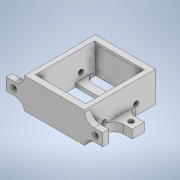
# Autodesk Inventor part: Part1
Saved by Autodesk Inventor 2022.6 (Build 266554000, 554)
## iProperties
Created: 2026-03-13
Part Number: Part1
Material: Generic
Document SubType Name: Modeling
Designer: Dragos Macovei
Density: 1 g/cm^3
Appearance: Default
Author: Dragos Macovei
Autodesk Inventor part; units mm, degrees
ref_plane "YZ Plane" through (0, 0, 0) normal (1, 0, 0) x (0, 1, 0)
ref_plane "XZ Plane" through (0, 0, 0) normal (0, 1, 0) x (-1, 0, 0)
ref_plane "XY Plane" through (0, 0, 0) normal (0, 0, 1) x (1, 0, 0)
sketch "Sketch1" plane through (0, 0, 0) normal (0, 1, 0) x (-1, 0, 0)
  line L0 (0, 0) -> (41, 0)
  line L1 (41, 0) -> (41, 50)
  line L2 (41, 50) -> (0, 50)
  line L3 (0, 50) -> (0, 0)
  line L4 (45, 54) -> (-4, 54)
  line L5 (-4, 54) -> (-4, -4)
  line L6 (-4, -4) -> (45, -4)
  line L7 (45, -4) -> (45, 54)
  point P0 (20.5, 50)
  dimension "d0" = 50
  dimension "d1" = 41
  dimension "d2" = 4
  dimension "d3" = 4
  dimension "d4" = 4
  dimension "d5" = 4
  constraints: 16 end point, 4 parallel, 2 horizontal, 2 perpendicular, 1 midpoint
  measures "d0" distance of L0.end L1.end
  measures "d1" distance of L1.end L2.end
  measures "d2" distance from line of L4 point (20.5, 50)
  measures "d3" distance between parallel lines of L1 L7
  measures "d4" distance between parallel lines of L6 L0
  measures "d5" distance between parallel lines of L5 L3
extrude "Extrusion1" add sketch "Sketch1" along normal blind 23
sketch "Sketch2" plane through (0, 0, 0) normal (0, -1, 0) x (1, 0, 0)
  line L0 (4, 54) -> (4, -4) projected
  line L1 (4, 54) -> (4, -4) projected
  line L2 (-45, 54) -> (4, 54) projected
  line L3 (-45, -4) -> (-45, 54) projected
  line L4 (4, -4) -> (-45, -4) projected
  line L5 (0, 0) -> (0, 50) projected
  line L6 (-41, 0) -> (0, 0) projected
  line L7 (-41, 50) -> (-41, 0) projected
  line L8 (0, 50) -> (-41, 50) projected
  line L9 (0, 0) -> (0, 50) projected
  line L10 (0, 40) -> (-41, 40)
  line L11 (-41, 40) -> (-41, 33.5)
  line L12 (-41, 33.5) -> (0, 33.5)
  line L13 (0, 33.5) -> (0, 40)
  line L14 (-41, 50) -> (-41, 0) projected
  line L15 (0, 16.5) -> (-41, 16.5)
  line L16 (-41, 16.5) -> (-41, 10)
  line L17 (-41, 10) -> (0, 10)
  line L18 (0, 10) -> (0, 16.5)
  point P0 (-8.1981, 16.5)
  point P1 (-8.1981, 33.5)
  point P2 (-8.1981, 10)
  point P3 (-8.1981, 40)
  point P4 (-41, 36.75)
  dimension "d8" = 16.5
  dimension "d9" = 16.5
  dimension "d10" = 10
  dimension "d11" = 10
  constraints: 16 end point, 4 parallel, 4 point on line, 2 horizontal, 2 perpendicular, 1 midpoint
  measures "d8" distance from line of L6 point (-8.198, 16.5)
  measures "d9" distance from line of point (-8.198, 33.5) L8
  measures "d10" distance from line of L6 point (-8.198, 10)
  measures "d11" distance from line of L8 point (-8.198, 40)
extrude "Extrusion2" add sketch "Sketch2" against normal blind 3 contours L17 L7 L15 L5 | L12 L7 L10 L5
fillet "Fillet1" radius 8 4 edges at (-41, 1.5, 40) (0, 1.5, 40) (0, 1.5, 10) (-41, 1.5, 10)
sketch "Sketch3" plane through (-45, 0, -4) normal (-1, 0, 0) x (0, 0, 1)
  line L0 (54, 0) -> (54, 23) projected
  line L1 (4, 0) -> (4, 23) projected
  line L2 (20.5, 3) -> (6, 3) projected
  line L3 (52, 3) -> (37.5, 3) projected
  circle A0 centre (16, 8.3) radius 2.1
  circle A1 centre (42, 8.3) radius 2.1
  dimension "d57" = 0
  dimension "d15" = 12
  dimension "d16" = 12
  dimension "d17" = 5.3
  dimension "d18" = 5.3
  dimension "d19" = 4.2
  dimension "d20" = 4.2
  constraints: 2 centre point, 2 coincident
  measures "d15" distance from line of L1 point (16, 8.3)
  measures "d16" distance from line of L0 point (42, 8.3)
  measures "d17" distance from line of L2 point (16, 8.3)
  measures "d18" distance from line of L3 point (42, 8.3)
  measures "d19" diameter of A0
  measures "d20" diameter of A1
extrude "Extrusion3" cut sketch "Sketch3" against normal through all
sketch "Sketch4" plane through (-45, 0, 54) normal (0, 0, 1) x (1, 0, 0)
  point P0 (45, 0)
sketch "Sketch5" plane through (-45, 0, 54) normal (0, 0, 1) x (1, 0, 0)
  line L0 (0, 0) -> (49, 0) projected
  line L1 (49, 0) -> (49, 23) projected
  line L2 (0, 23) -> (49, 23) projected
  line L3 (0, 0) -> (0, 23) projected
  line L4 (0, 0) -> (0, 23) projected
  line L5 (0, 16.5) -> (-15, 16.5)
  line L6 (-15, 16.5) -> (-15, 6.5)
  line L7 (-15, 6.5) -> (0, 6.5)
  line L8 (0, 6.5) -> (0, 16.5)
  line L9 (49, 0) -> (49, 23) projected
  line L10 (49, 6.5) -> (64, 6.5)
  line L11 (64, 6.5) -> (64, 16.5)
  line L12 (64, 16.5) -> (49, 16.5)
  line L13 (49, 16.5) -> (49, 6.5)
  point P0 (45, 0)
  point P1 (-15, 11.5)
  point P2 (64, 11.5)
  point P3 (49, 11.5)
  point P4 (0, 11.5)
  point P5 (0, 6.5)
  point P6 (0, 16.5)
  dimension "d23" = 15
  dimension "d24" = 15
  dimension "d25" = 10
  dimension "d26" = 6.5
  constraints: 16 end point, 4 midpoint, 4 parallel, 4 point on line, 2 horizontal, 2 perpendicular
  measures "d23" distance of L11.end L12.end
  measures "d24" distance of L5.start L5.end
  measures "d25" distance of L5.end L6.end
  measures "d26" distance of L5.start L2.start
extrude "Extrusion4" add sketch "Sketch5" against normal blind 5 contours L7 L6 L5 L3 | L1 L12 L11 L10
fillet "Fillet2" radius 8 4 edges at (-45, 16.5, 51.5) (-45, 6.5, 51.5) (4, 6.5, 51.5) (4, 16.5, 51.5)
sketch "Sketch6" plane through (-45, 0, 49) normal (0, 0, -1) x (-1, 0, 0)
  line L0 (0, 0) -> (-49, 0) projected
  arc A0 (-49, 0) -> (-56.8581, 6.5) centre (-56.8581, -1.5) ccw projected
  line L1 (-56.8581, 6.5) -> (-64, 6.5) projected
  line L2 (-64, 6.5) -> (-64, 16.5) projected
  line L3 (-64, 16.5) -> (-56.8581, 16.5) projected
  arc A1 (-56.8581, 16.5) -> (-49, 23) centre (-56.8581, 24.5) ccw projected
  line L4 (0, 23) -> (-49, 23) projected
  arc A2 (0, 23) -> (7.8581, 16.5) centre (7.8581, 24.5) ccw projected
  line L5 (7.8581, 16.5) -> (15, 16.5) projected
  line L6 (15, 16.5) -> (15, 6.5) projected
  line L7 (15, 6.5) -> (7.8581, 6.5) projected
  arc A3 (7.8581, 6.5) -> (0, 0) centre (7.8581, -1.5) ccw projected
  circle A4 centre (9, 11.5) radius 2.5
  circle A5 centre (-58, 11.5) radius 2.5
  line L8 (-64, 16.5) -> (-64, 6.5) projected
  point P0 (-45, 0)
  point P1 (15, 11.5)
  point P2 (-64, 11.5)
  dimension "d30" = 6
  dimension "d31" = 5
  dimension "d32" = 6
  dimension "d33" = 5
  constraints: 2 centre point, 2 midpoint
  measures "d30" distance of point (15, 11.5) A4.centre
  measures "d31" diameter of A4
  measures "d32" distance of point (-64, 11.5) A5.centre
  measures "d33" diameter of A5
extrude "Extrusion5" cut sketch "Sketch6" against normal through all contours A4 | A5
sketch "Sketch7" plane through (0, 0, 0) normal (0, -1, 0) x (1, 0, 0)
  line L0 (-41, 33.5) -> (-41, 16.5) projected
  line L1 (-41, 33.5) -> (0, 33.5) projected
  line L2 (0, 16.5) -> (0, 33.5) projected
  line L3 (0, 16.5) -> (-41, 16.5) projected
  line L4 (-41, 50) -> (-41, 48) projected
  line L5 (0, 50) -> (-41, 50) projected
  line L6 (0, 48) -> (0, 50) projected
  arc A0 (-8, 40) -> (0, 48) centre (-8, 48) ccw projected
  line L7 (-8, 40) -> (-33, 40) projected
  arc A1 (-41, 48) -> (-33, 40) centre (-33, 48) ccw projected
  line L8 (4, 54) -> (4, 49) projected
  line L9 (-45, 54) -> (4, 54) projected
  line L10 (-45, 49) -> (-45, 54) projected
  line L11 (-45, -4) -> (-45, 49) projected
  line L12 (4, -4) -> (-45, -4) projected
  line L13 (4, 49) -> (4, -4) projected
  line L14 (-33, 10) -> (-8, 10) projected
  arc A2 (0, 2) -> (-8, 10) centre (-8, 2) ccw projected
  line L15 (0, 0) -> (0, 2) projected
  line L16 (-41, 0) -> (0, 0) projected
  line L17 (-41, 2) -> (-41, 0) projected
  arc A3 (-33, 10) -> (-41, 2) centre (-33, 2) ccw projected
  line L18 (11.8581, 54) -> (19, 54) projected
  line L19 (-60, 54) -> (-60, 49) projected
  line L20 (19, 54) -> (19, 49) projected
  line L21 (19, 30) -> (4, 30)
  line L22 (4, 30) -> (4, 20)
  line L23 (4, 20) -> (19, 20)
  line L24 (19, 20) -> (19, 30)
  line L25 (-45, -4) -> (-45, 49) projected
  line L26 (-45, 30) -> (-60, 30)
  line L27 (-60, 30) -> (-60, 20)
  line L28 (-60, 20) -> (-45, 20)
  line L29 (-45, 20) -> (-45, 30)
  point P0 (4, 51.5)
  point P1 (19, 25)
  point P2 (-45, 22.5)
  point P3 (-60, 25)
  point P4 (-52.5, 20)
  point P5 (-52.5, 30)
  point P6 (11.5, 20)
  dimension "d36" = 15
  dimension "d37" = 15
  dimension "d38" = 15
  dimension "d39" = 10
  dimension "d40" = 10
  dimension "d41" = 24
  dimension "d42" = 24
  constraints: 16 end point, 7 midpoint, 4 parallel, 2 horizontal, 2 perpendicular, 2 point on line
  measures "d36" distance from line of point (4, 51.5) L20
  measures "d37" distance from line of L13 point (19, 25)
  measures "d38" horizontal distance of point (-45, 22.5) point (-60, 25)
  measures "d39" distance of point (-52.5, 20) point (-52.5, 30)
  measures "d40" distance from line of point (11.5, 20) L21
  measures "d41" distance of L12.start L22.end
  measures "d42" distance of L11.start L28.end
extrude "Extrusion6" add sketch "Sketch7" against normal blind 7 contours L21 L24 L23 L13 | L11 L28 L27 L26
fillet "Fillet3" radius 8 4 edges at (4, 3.5, 20) (4, 3.5, 30) (-45, 3.5, 30) (-45, 3.5, 20)
sketch "Sketch8" plane through (0, 7, 0) normal (0, 1, 0) x (1, 0, 0)
  line L0 (12, -30) -> (19, -30) projected
  line L1 (19, -30) -> (19, -20) projected
  line L2 (19, -20) -> (12, -20) projected
  arc A0 (4.1718, -13.6492) -> (12, -20) centre (12, -12) ccw projected
  line L3 (4.1718, -13.6492) -> (4, -13.6492) projected
  line L4 (4, -36.3508) -> (4, -13.6492) projected
  line L5 (4.1718, -36.3508) -> (4, -36.3508) projected
  arc A1 (12, -30) -> (4.1718, -36.3508) centre (12, -38) ccw projected
  line L6 (-53, -20) -> (-60, -20) projected
  line L7 (-60, -20) -> (-60, -30) projected
  line L8 (-60, -30) -> (-53, -30) projected
  arc A2 (-45.1718, -36.3508) -> (-53, -30) centre (-53, -38) ccw projected
  line L9 (-45.1718, -36.3508) -> (-45, -36.3508) projected
  line L10 (-45, -13.6492) -> (-45, -36.3508) projected
  line L11 (-45.1718, -13.6492) -> (-45, -13.6492) projected
  arc A3 (-53, -20) -> (-45.1718, -13.6492) centre (-53, -12) ccw projected
  circle A4 centre (13, -25) radius 2.1
  circle A5 centre (-54, -25) radius 2.1
  point P0 (0, 0)
  dimension "d46" = 4.2
  dimension "d47" = 4.2
  dimension "d48" = 6
  dimension "d49" = 6
  constraints: 2 centre point
  measures "d46" diameter of A4
  measures "d47" diameter of A5
  measures "d48" distance from line of L7 A5.centre
  measures "d49" distance from line of L1 A4.centre
extrude "Extrusion7" cut sketch "Sketch8" against normal through all contours A4 | A5
sketch "Sketch9" plane through (0, 23, 0) normal (0, 1, 0) x (1, 0, 0)
  line L0 (4, -54) -> (4, -49) projected
  line L1 (4, -49) -> (4, 4) projected
  line L2 (4, 4) -> (-45, 4) projected
  line L3 (-45, 4) -> (-45, -49) projected
  line L4 (-45, -49) -> (-45, -54) projected
  line L5 (-45, -54) -> (4, -54) projected
  line L6 (0, 0) -> (0, -50) projected
  line L7 (0, -50) -> (-41, -50) projected
  line L8 (-41, -50) -> (-41, 0) projected
  line L9 (-41, 0) -> (0, 0) projected
  line L10 (0, -1) -> (-41, -1)
  line L11 (-41, -1) -> (-41, -49)
  line L12 (-41, -49) -> (0, -49)
  line L13 (0, -49) -> (0, -1)
  dimension "d52" = 1
  dimension "d53" = 1
  dimension "d54" = 0
  dimension "d55" = 0
  constraints: 8 end point, 2 parallel, 1 horizontal, 1 perpendicular
  measures "d52" distance between parallel lines of L9 L10
  measures "d53" distance between parallel lines of L7 L12
  measures "d54" distance between parallel lines of L6 L13
  measures "d55" distance between parallel lines of L8 L11
extrude "Extrusion8" add sketch "Sketch9" along normal blind 2 contours L5 L4 L3 L2 L1 L0 | L6 L10 L8 L9 | L6 L7 L8 L12
fillet "Fillet4" radius 1 2 edges at (-20.5, 23, 0) (-20.5, 23, 50)
equation "\"d3\" = d2"
equation "\"d4\" = d3"
equation "\"d5\" = d2"
equation "\"d9\" = d8"
equation "\"d11\" = d10"
equation "\"d16\" = d15"
equation "\"d18\" = d17"
equation "\"d32\" = d30"
equation "\"d33\" = d31"
equation "\"d37\" = d36"
equation "\"d38\" = d36"
equation "\"d42\" = d41"
body "Solid1"
